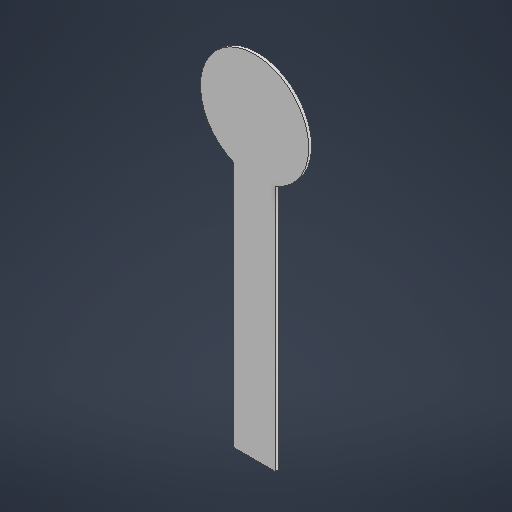
# Autodesk Inventor part: Pressure Sensor
Saved by Autodesk Inventor 2026.2 (Build 302298000, 298)
## iProperties
Created: 2026-11-10
Part Number: Pressure Sensor
Material: Generic
Document SubType Name: Modeling
Designer: Carro
Density: 1 g/cm^3
Appearance: Default
Author: Carro
Autodesk Inventor part; units mm, degrees
ref_plane "YZ Plane" through (0, 0, 0) normal (1, 0, 0) x (0, 1, 0)
ref_plane "XZ Plane" through (0, 0, 0) normal (0, 1, 0) x (-1, 0, 0)
ref_plane "XY Plane" through (0, 0, 0) normal (0, 0, 1) x (1, 0, 0)
sketch "Sketch1" plane through (0, 0, 0) normal (0, 0, 1) x (1, 0, 0)
  circle A0 centre (0, 0) radius 9.271
  line L0 (-3.556, 0) -> (3.556, 0)
  line L1 (-3.556, 0) -> (3.556, 0)
  line L2 (3.556, 0) -> (3.556, -50.8)
  line L3 (3.556, -50.8) -> (-3.556, -50.8)
  line L4 (-3.556, -50.8) -> (-3.556, 0)
  point P0 (3.556, -8.5619)
  point P1 (-3.556, -8.5619)
  dimension "d0" = 18.542
  dimension "d1" = 7.112
  dimension "d2" = 50.8
  constraints: 10 end point, 2 horizontal, 2 parallel, 1 centre point, 1 coincident, 1 midpoint, 1 perpendicular
  measures "d0" diameter of A0
  measures "d1" distance of L0.start L0.end
  measures "d2" distance of L0.end L2.end
extrude "Extrusion1" add sketch "Sketch1" along normal mid plane 0.4826
body "Solid1"
